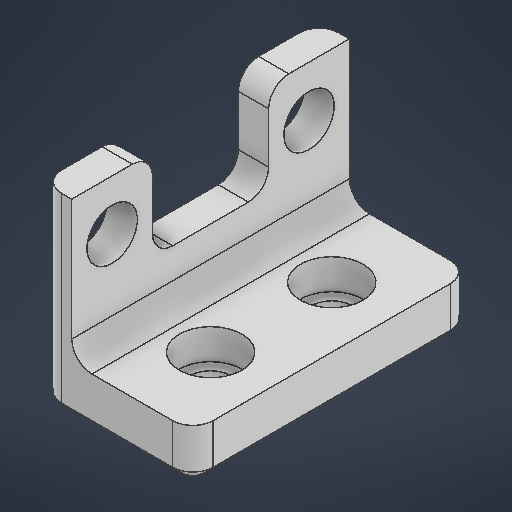
# Autodesk Inventor part: vl53_hoder
Saved by Autodesk Inventor 2026.2 (Build 302298010, 298A)
## iProperties
Created: 2026-04-23
Part Number: vl53_hoder
Material: 일반
Document SubType Name: Modeling
Designer: work
Density: 1 g/cm^3
Appearance: 기본값
Author: work
Autodesk Inventor part; units mm, degrees
ref_plane "YZ Plane" through (0, 0, 0) normal (1, 0, 0) x (0, 1, 0)
ref_plane "XZ Plane" through (0, 0, 0) normal (0, 1, 0) x (-1, 0, 0)
ref_plane "XY Plane" through (0, 0, 0) normal (0, 0, 1) x (1, 0, 0)
sketch "스케치1" plane through (0, 0, 0) normal (1, 0, 0) x (0, 1, 0)
  line L0 (0, 9.75) -> (0, -9.75) construction
  circle A0 centre (0, -9.75) radius 2.5
  line L1 (-4, 0) -> (-4, -5.75)
  line L2 (-4, -5.75) -> (5, -5.75)
  line L3 (5, -5.75) -> (5, -13.75)
  line L4 (5, -13.75) -> (-4.9443, -13.75)
  line L5 (-4.9443, -13.75) -> (-14, -13.75)
  line L6 (-14, -13.75) -> (-14, 0)
  line L7 (0, 0) -> (-3.7785, 0) construction
  line L8 (0, -9.75) -> (0, 9.75) construction
  circle A1 centre (0, 9.75) radius 2.5
  line L9 (-4, 0) -> (-4, 5.75)
  line L10 (-4, 5.75) -> (5, 5.75)
  line L11 (5, 5.75) -> (5, 13.75)
  line L12 (5, 13.75) -> (-4.9443, 13.75)
  line L13 (-4.9443, 13.75) -> (-14, 13.75)
  line L14 (-14, 13.75) -> (-14, 0)
  dimension "d0" = 19.5
  dimension "d2" = 5
  dimension "d3" = 4
  dimension "d4" = 10
  dimension "d5" = 5
  dimension "d6" = 4
  dimension "d7" = 4
  constraints: 30 end point, 8 symmetric about line, 5 perpendicular, 2 centre point, 2 coincident, 2 point on line, 2 vertical, 1 midpoint, 1 other
  measures "d0" distance of L0.start L0.end
  measures "d2" diameter of A0
  measures "d3" distance between parallel lines of L0 L1
  measures "d4" distance between parallel lines of L6 L1
  measures "d5" distance from line of L3 L0.end
  measures "d6" distance from line of L2 L0.end
  measures "d7" distance from line of A0.centre L4
extrude "돌출1" add sketch "스케치1" along normal blind 3
sketch "스케치2" plane through (0, -14, -13.75) normal (0, -1, 0) x (1, 0, 0)
  line L0 (3, 19.5) -> (3, 27.5) projected
  line L1 (3, 27.5) -> (15, 27.5)
  line L2 (15, 27.5) -> (15, 0)
  line L3 (15, 0) -> (3, 0)
  line L4 (3, 0) -> (3, 27.5)
  line L5 (3, 13.75) -> (15, 13.75) construction
  line L6 (9, 19.75) -> (9, 7.75) construction
  circle A0 centre (9, 19.75) radius 2
  circle A1 centre (9, 7.75) radius 2
  point P0 (0, 13.75)
  point P1 (9, 13.75)
  point P2 (3, 0)
  point P3 (3, 19.5)
  dimension "d10" = 12
  dimension "d11" = 4
  dimension "d12" = 4
  dimension "d13" = 6
  constraints: 12 end point, 4 midpoint, 2 centre point, 2 coincident, 2 parallel, 1 horizontal, 1 perpendicular, 1 point on line, 1 vertical
  measures "d10" distance of L6.start L6.end
  measures "d11" diameter of A0
  measures "d12" diameter of A1
  measures "d13" distance from line of L2 L6.end
extrude "돌출2" add sketch "스케치2" against normal blind 5
sketch "스케치3" plane through (0, -9, -13.75) normal (0, 1, 0) x (1, 0, 0)
  circle A0 centre (9, -19.75) radius 2 projected
  circle A1 centre (9, -7.75) radius 2 projected
  point P0 (0, -13.75)
  point P1 (9, -19.75)
  point P2 (9, -7.75)
  constraints: 2 coincident
hole "구멍1" at (9, -9, 6) at (9, -9, -6) direction (0, -1, 0) diameter 3.8 end through all counterbore diameter 6.2 counterbore depth 3
fillet "모깎기1" radius 2 9 edges at (15, -11.5, -13.75) (0, -4.5, -13.75) (15, -11.5, 13.75) (0, -4.5, 13.75) (1.5, -4, 5.75) (1.5, 5, 5.75) (1.5, 5, -5.75) (1.5, -4, -5.75) (3, -9, 0)
chamfer "모따기1" distance 1 angle 45 8 edges at (15, -14, 0) (14.4142, -14, 13.1642) (7.5, -14, 13.75) (0.5858, -14, 13.1642) (0, -14, 0) (0.5858, -14, -13.1642) (7.5, -14, -13.75) (14.4142, -14, -13.1642)
